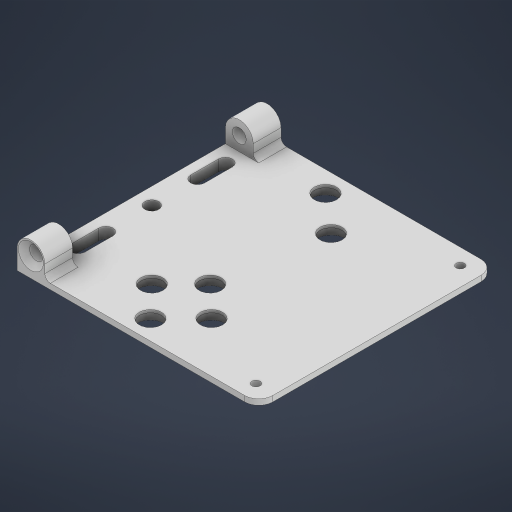
# Autodesk Inventor part: КрышкаНизV2
Saved by Autodesk Inventor 2024 (Build 280153000, 153)
## iProperties
Created: 2026-05-30
Part Number: КрышкаНизV2
Material: Типовые
Document SubType Name: Modeling
Designer: mitm
Density: 1 g/cm^3
Appearance: По умолчанию
Author: mitm
Autodesk Inventor part; units mm, degrees
ref_plane "YZ Plane" through (0, 0, 0) normal (1, 0, 0) x (0, 1, 0)
ref_plane "XZ Plane" through (0, 0, 0) normal (0, 1, 0) x (-1, 0, 0)
ref_plane "XY Plane" through (0, 0, 0) normal (0, 0, 1) x (1, 0, 0)
sketch "Эскиз1" plane through (0, 0, 0) normal (0, 1, 0) x (-1, 0, 0)
  line L0 (39, 42.5) -> (-29, 42.5)
  line L1 (-39, 32.5) -> (-39, -32.5)
  line L2 (-29, -42.5) -> (39, -42.5)
  line L3 (-29, 42.5) -> (-34, 42.5)
  line L4 (-39, 37.5) -> (-39, 32.5)
  circle A0 centre (-32.25, 36.75) radius 1.5
  line L5 (-29, -42.5) -> (-34, -42.5)
  line L6 (-39, -32.5) -> (-39, -37.5)
  arc A1 (-34, 42.5) -> (-39, 37.5) centre (-34, 37.5) ccw
  arc A2 (-39, -37.5) -> (-34, -42.5) centre (-34, -37.5) ccw
  circle A3 centre (-32.25, -36.75) radius 1.5
  line L7 (36, 40.5) -> (-15, 40.5)
  line L8 (-15, 40.5) -> (-15, -40.5)
  line L9 (-15, -40.5) -> (36, -40.5)
  line L10 (36, -40.5) -> (36, 40.5)
  line L11 (36, -40.5) -> (18.5, -40.5)
  circle A4 centre (14.5, -35) radius 4
  line L12 (36, -40.5) -> (5, -40.5)
  circle A5 centre (1, -23.5) radius 4
  line L13 (36, 40.5) -> (36, 28.5)
  line L14 (36, 40.5) -> (36, 39.5)
  circle A6 centre (17.5, 24.5) radius 4
  circle A7 centre (7, 14) radius 4
  circle A8 centre (-4, 24.5) radius 4
  circle A9 centre (7, 35.5) radius 4
  line L15 (39, 42.5) -> (48, 42.5)
  line L16 (48, 42.5) -> (48, -42.5)
  line L17 (48, -42.5) -> (39, -42.5)
  line L18 (48, -42.5) -> (46, -42.5)
  line L19 (36, -40.5) -> (46, -40.5)
  line L20 (46, -40.5) -> (46, 40.5)
  line L21 (46, 40.5) -> (36, 40.5)
  line L22 (38, -40.5) -> (38, 40.5)
  line L23 (46, 40.5) -> (38, 40.5)
  line L24 (38, 40.5) -> (38, -40.5)
  line L25 (38, -40.5) -> (46, -40.5)
  line L26 (46, -40.5) -> (46, 40.5)
  circle A10 centre (42, 0) radius 2.5
  circle A11 centre (7, 35.5) radius 5
  circle A12 centre (17.5, 24.5) radius 5
  circle A13 centre (7, 14) radius 5
  circle A14 centre (-4, 24.5) radius 5
  circle A15 centre (1, -23.5) radius 5
  circle A16 centre (14.5, -35) radius 5
  line L27 (46, -40.5) -> (38, -40.5)
  line L28 (38, -40.5) -> (38, -2.5)
  line L29 (46, -2.5) -> (46, -40.5)
  line L30 (46, 40.5) -> (38, 40.5)
  line L31 (38, 40.5) -> (38, 2.5)
  line L32 (46, 2.5) -> (46, 40.5)
  line L33 (39.5, -26.5) -> (39.5, -16.5)
  line L34 (44.5, -16.5) -> (44.5, -26.5)
  line L35 (39.5, 16.5) -> (39.5, 26.5)
  line L36 (44.5, 26.5) -> (44.5, 16.5)
  arc A17 (39.5, -26.5) -> (44.5, -26.5) centre (42, -26.5) ccw
  arc A18 (44.5, -16.5) -> (39.5, -16.5) centre (42, -16.5) ccw
  arc A19 (39.5, 16.5) -> (44.5, 16.5) centre (42, 16.5) ccw
  arc A20 (44.5, 26.5) -> (39.5, 26.5) centre (42, 26.5) ccw
  point P0 (7, 40.5)
  dimension "d11" = 3
  dimension "d12" = 5
  dimension "d20" = 3
  dimension "d23" = 81
  dimension "d54" = 9
  dimension "d55" = 2
  dimension "d57" = 5
  dimension "d58" = 10
  dimension "d59" = 10
  dimension "d60" = 10
  dimension "d61" = 10
  dimension "d62" = 10
  constraints: 74 end point, 21 centre point, 13 tangent, 12 point on circle, 11 perpendicular, 10 point on line, 9 parallel, 6 coincident, 6 horizontal, 1 equal radius
  measures "d11" diameter of A0
  measures "d12" radius of A1
  measures "d20" diameter of A3
  measures "d23" distance of L8.end L7.end
  measures "d54" distance of L0.start L15.end
  measures "d55" distance of L16.end L18.end
  measures "d57" diameter of A10
  measures "d58" diameter of A12
  measures "d59" diameter of A13
  measures "d60" diameter of A14
  measures "d61" diameter of A15
  measures "d62" diameter of A16
extrude "Выдавливание5" add sketch "Эскиз1" along normal blind 2 contours L15 L16 L17 L2 L5 A2 L6 L1 L4 A1 L3 L0 | A0 | A3 | A11 | L10 L9 L8 L7 | L21 L22 L19 L10 | L21 L20 L19 L22 | A4 | A5 | A6 | A7 | A8 | A9 | A10 | A12 | A13 | A14 | A15 | A16 | L33 A18 L34 A17 | L35 A20 L36 A19
extrude "Выдавливание6" cut sketch "Эскиз1" along normal blind 2 contours A4 | A5 | A6 | A7 | A8 | A9
extrude "Выдавливание7" add sketch "Эскиз1" against normal blind 2 contours L10 L9 L8 L7 | L21 L20 L19 L22
extrude "Выдавливание8" cut sketch "Эскиз1" along normal blind 1 contours A11 | A12 | A13 | A14 | A15 | A16
extrude "Выдавливание9" cut sketch "Эскиз1" along normal blind 2 contours A0 | A3 | A10 | L33 A18 L34 A17 | L35 A20 L36 A19
sketch "Эскиз2" plane through (0, 2, 0) normal (0, 1, 0) x (1, 0, 0)
  line L0 (-48, -42.5) -> (34, -42.5) projected
  line L1 (-48, -42.5) -> (-38, -42.5)
  line L2 (-38, -42.5) -> (-38, -32.5)
  line L3 (-38, -32.5) -> (-48, -32.5)
  line L4 (-48, -32.5) -> (-48, -42.5)
  line L5 (34, 42.5) -> (-48, 42.5) projected
  line L6 (-48, 42.5) -> (-38, 42.5)
  line L7 (-38, 42.5) -> (-38, 32.5)
  line L8 (-38, 32.5) -> (-48, 32.5)
  line L9 (-48, 32.5) -> (-48, 42.5)
  point P0 (0, 0)
  dimension "d79" = 10
  dimension "d80" = 10
  dimension "d81" = 10
  dimension "d82" = 10
  constraints: 16 end point, 4 parallel, 2 horizontal, 2 perpendicular
  measures "d79" distance of L3.end L2.end
  measures "d80" distance of L2.end L1.end
  measures "d81" distance of L7.end L8.end
  measures "d82" distance of L6.end L7.end
extrude "Выдавливание10" add sketch "Эскиз2" along normal blind 10
sketch "Эскиз3" plane through (34, 0, -42.5) normal (0, 0, -1) x (-1, 0, 0)
  line L0 (72, 12) -> (82, 12) projected
  line L1 (72, 2) -> (0, 2) projected
  line L2 (82, 12) -> (72, 12)
  line L3 (72, 12) -> (72, 2)
  line L4 (72, 2) -> (82, 2)
  line L5 (82, 2) -> (82, 12)
  circle A0 centre (77, 7) radius 5
  circle A1 centre (77, 7) radius 2.5
  point P0 (34, 0)
  point P1 (77, 12)
  point P2 (82, 7)
  point P3 (72, 7)
  dimension "d85" = 5
  constraints: 8 end point, 3 tangent, 2 centre point, 2 parallel, 1 coincident, 1 horizontal, 1 perpendicular
  measures "d85" diameter of A1
extrude "Выдавливание11" cut sketch "Эскиз3" against normal blind 100 contours L0 A0 L3 | L0 L5 A0 | A1
chamfer "Фаска1" distance 2 angle 45 2 edges at (-40.5, 7, -42.5) (-40.5, 7, 42.5)
fillet "Сопряжение1" radius 2 2 edges at (-38, 2, 37.5) (-38, 2, -37.5)
